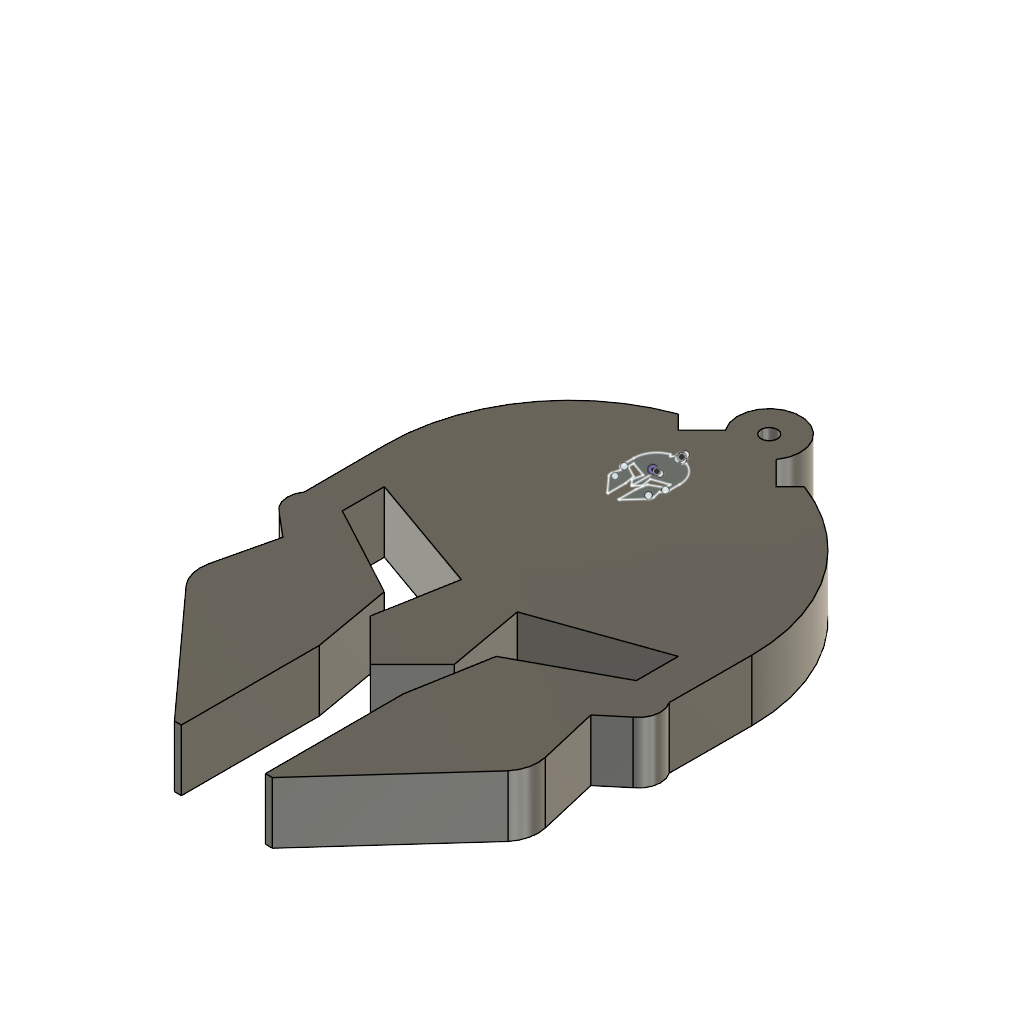
llavero-espartano (Autodesk Fusion 360 design; units mm, degrees)
part number: 2026-10-01-10-02-46-327
Autodesk Fusion 360 part; units mm, degrees
sketch "Boceto1" plane through (0, 0, 0) normal (0, 0, 1) x (1, 0, 0)
sketch "Boceto2" plane through (0, 0, 0) normal (0, 0, 1) x (1, 0, 0)
  arc A0 (-0.5, 2.5) -> (-2.2106, 0.0408) centre (0.4001, 0.0494) ccw
  line L0 (-2.2106, 0.0408) -> (-2.2068, -1.136)
  arc A1 (-2.2068, -1.136) -> (-2.1283, -1.5747) centre (-1.9539, -1.3171) ccw
  line L1 (-2.1283, -1.5747) -> (-1.8, -1.85)
  line L2 (-1.8, -1.85) -> (-2, -2.7)
  arc A2 (-2, -2.7) -> (-1.9, -3.1328) centre (-1.5111, -2.815) ccw
  line L3 (-1.9, -3.1328) -> (-0.3, -4.9)
  line L4 (-0.3, -4.9) -> (-0.2, -4.9)
  line L5 (-0.2, -4.9) -> (-0.2, -2.9281)
  line L6 (-0.2, -2.9281) -> (-0.4, -1.8)
  line L7 (-0.4, -1.8) -> (-1.7, -1.1)
  line L8 (-1.7, -1.1) -> (-1.7, -0.5)
  line L9 (-1.7, -0.5) -> (0, -1.1)
  line L10 (0, -1.1) -> (-0.2, -2.2)
  line L11 (-0.2, -2.2) -> (0.3, -2.7)
  line L12 (-0.5, 2.5) -> (-0.3, 2.3)
  line L13 (-0.3, 2.3) -> (0.0367, 2.6367)
  line L14 (0.4001, 0.0494) -> (0.4001, -2.8001)
  line L15 (0.3, -2.7) -> (0.4001, -2.8001)
  arc A3 (0.4001, 3.0164) -> (0.4001, 2.7831) centre (0.4001, 2.8998) ccw
  arc A4 (0.4001, 3.3485) -> (0.4001, 2.4511) centre (0.4001, 2.8998) ccw
  line L16 (0.4001, 2.4511) -> (0.4001, 2.7831)
  line L17 (0.4001, 3.0164) -> (0.4001, 3.3485)
  arc A5 (2.7002, -3.1328) -> (2.8002, -2.7) centre (2.3113, -2.815) ccw
  line L18 (1.0002, -4.9) -> (1.0002, -2.9281)
  line L19 (1.1002, 2.3) -> (0.7635, 2.6367)
  arc A6 (2.9285, -1.5747) -> (3.007, -1.136) centre (2.754, -1.3171) ccw
  line L20 (2.5002, -0.5) -> (0.8002, -1.1)
  line L21 (2.9285, -1.5747) -> (2.6002, -1.85)
  line L22 (1.2002, -1.8) -> (2.5002, -1.1)
  arc A7 (3.0108, 0.0408) -> (1.3002, 2.5) centre (0.4001, 0.0494) ccw
  arc A8 (0.4001, 2.4511) -> (0.4001, 3.3485) centre (0.4001, 2.8998) ccw
  line L23 (3.0108, 0.0408) -> (3.007, -1.136)
  line L24 (1.0002, -2.2) -> (0.5002, -2.7)
  arc A9 (0.4001, 2.7831) -> (0.4001, 3.0164) centre (0.4001, 2.8998) ccw
  line L25 (2.6002, -1.85) -> (2.8002, -2.7)
  line L26 (2.7002, -3.1328) -> (1.1002, -4.9)
  line L27 (1.0002, -2.9281) -> (1.2002, -1.8)
  line L28 (1.3002, 2.5) -> (1.1002, 2.3)
  line L29 (2.5002, -1.1) -> (2.5002, -0.5)
  line L30 (0.8002, -1.1) -> (1.0002, -2.2)
  line L31 (1.1002, -4.9) -> (1.0002, -4.9)
  line L32 (0.5002, -2.7) -> (0.4001, -2.8001)
  point P0 (0.8002, 0)
  dimension "d1" = 0.3111
  dimension "d2" = 0.5022
  dimension "d3" = 0.1166
  dimension "d4" = 2.6107
  dimension "d5" = 2.6069
  dimension "d6" = 2.5284
  dimension "d7" = 2.354
  dimension "d8" = 2.3001
  dimension "d9" = 2.2001
  dimension "d10" = 2.1001
  dimension "d11" = 1.9112
  dimension "d12" = 0.9001
  dimension "d13" = 0.8001
  dimension "d14" = 0.7001
  dimension "d15" = 0.6001
  dimension "d16" = 0.3634
  dimension "d17" = 0.4001
  dimension "d18" = 0.4487
  dimension "d19" = 0.0494
  dimension "d20" = 169.946
  dimension "d21" = 99.135
  dimension "d22" = 4.1014
  dimension "d23" = 3.1822
  dimension "d24" = 2.9774
  dimension "d25" = 1.8994
  dimension "d26" = 1.8494
  dimension "d27" = 1.6241
  dimension "d28" = 1.1494
  dimension "d29" = 0.5494
  dimension "d30" = 0.1
  dimension "d31" = 0.1001
  constraint tangent A0 L0
  constraint tangent L2 A2
  constraint horizontal L4
  constraint perpendicular L4 L5
  constraint perpendicular L4 L8
  constraint perpendicular L12 L13
  constraint coincident A0.centre L14.start
  constraint vertical L14
  constraint parallel L11 L15
  constraint parallel L14 L16
  constraint coincident A3.centre L16
  constraint concentric A3 A4
  constraint coincident L13.end A4
  constraint collinear L16 L17
  constraint symmetric origin L14 P0
  constraint symmetric A0.end L14 A7.start
  constraint symmetric A0.start L14 A7.end
  constraint symmetric A0 L14 A7
  constraint symmetric L0.end L14 A6.end
  constraint symmetric A1.end L14 A6.start
  constraint symmetric A1 L14 A6
  constraint symmetric L1.end L14 L21.end
  constraint symmetric L2.end L14 A5.end
  constraint symmetric A2.end L14 A5.start
  constraint symmetric A2 L14 A5
  constraint symmetric L3.end L14 L26.end
  constraint symmetric L4.end L14 L18.start
  constraint symmetric L5.end L14 L18.end
  constraint symmetric L6.end L14 L22.start
  constraint symmetric L7.end L14 L22.end
  constraint symmetric L8.end L14 L20.start
  constraint symmetric L9.end L14 L20.end
  constraint symmetric L10.end L14 L24.start
  constraint symmetric L11.end L14 L24.end
  constraint symmetric L12.end L14 L19.start
  constraint symmetric L13.end L14 L19.end
  constraint symmetric L14 A3.end L16.end
  constraint symmetric L14 A3.start L17.start
  constraint symmetric L14 A3 A9
  constraint symmetric L14 A4.end L16.start
  constraint symmetric L14 A4.start L17.end
  constraint symmetric L14 A4 A8
  constraint perpendicular L15 L32
  constraint tangent A4 A8
  constraint parallel L15 L19
  constraint vertical origin L9.end
  measures "d1" radius of A6
  measures "d2" radius of A5
  measures "d3" radius of A3
  measures "d4" radius of A0
  measures "d5" distance of L0.end L17
  measures "d6" distance of A1.end L17
  measures "d7" distance of A1.centre L17
  measures "d8" distance of A2.end L17
  measures "d9" distance of L1.end L17
  measures "d10" distance of L8 L17
  measures "d11" distance of A2.centre L17
  measures "d12" distance of A0.start L17
  measures "d13" distance of L6.end L17
  measures "d14" distance of L12.end L17
  measures "d15" distance of L10.end L17
  measures "d16" distance of L13.end L17
  measures "d17" distance of L17 P0
  measures "d18" vertical distance of A3.centre A4.start
  measures "d19" vertical distance of origin A0.centre
  measures "d20" angle of L18 L27
  measures "d21" angle of L20 L30
  measures "d22" distance of L11 L19
  measures "d23" vertical distance of A0.centre A5.start
  measures "d24" vertical distance of A0.centre L18.end
  measures "d25" vertical distance of A0.centre L21.end
  measures "d26" vertical distance of A0.centre L22.start
  measures "d27" vertical distance of A0.centre A6.start
  measures "d28" vertical distance of A0.centre L22.end
  measures "d29" vertical distance of A0.centre L20.start
  measures "d30" distance of L3.end L5
  measures "d31" distance of L11.end L17
extrude "Extruir1" add sketch "Boceto2" along normal blind 4 contours A0 L0 A1 L1 L2 A2 L3 L4 L5 L6 L7 L8 L9 L10 L11 L12 L13 L15 A4 A5 L18 L19 A6 L20 L21 L22 A7 A8 L23 L24 L25 L26 L27 L28 L29 L30 L31 L32
extrude "Extruir2" add sketch "Boceto2" along normal blind 4 contours A3 A4 L16 L17 | L16 L17 A8 A9
scale "Escala1" factor 8 about (3.007, -1.136, 4) bodies 1
extrude "Extruir3" cut 1 faces at (-9.4817, 15.6377, 4) along direction (0, 0, -1) blind 15
extrude "Extruir4" cut 1 faces at (-9.4817, 15.6377, -11) along direction (0, 0, -1) blind 10
